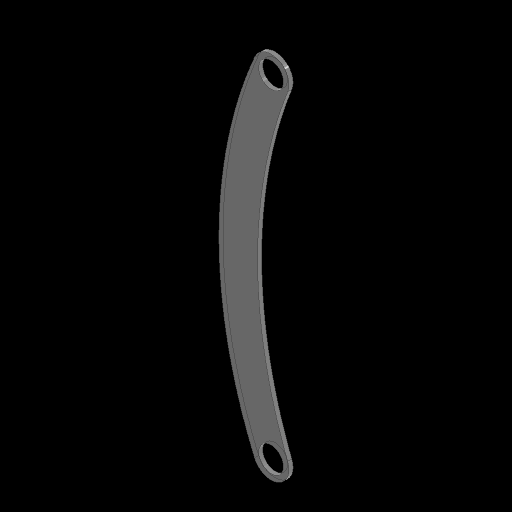
# Autodesk Inventor part: INTK_005_Right bar
Saved by Autodesk Inventor 2027.1 (Build 311270010, 270A)
## iProperties
Created: 2026-11-21
Part Number: INTK_005_Right bar
Material: Polycarbonate, Clear
Document SubType Name: Modeling
Designer: Stanley Ruangsuwan
Density: 1.2 g/cm^3
Appearance: Polycarbonate - Clear
Author: Stanley Ruangsuwan
Autodesk Inventor part; units mm, degrees
ref_plane "YZ Plane" through (0, 0, 0) normal (1, 0, 0) x (0, 1, 0)
ref_plane "XZ Plane" through (0, 0, 0) normal (0, 1, 0) x (-1, 0, 0)
ref_plane "XY Plane" through (0, 0, 0) normal (0, 0, 1) x (1, 0, 0)
sketch "Sketch1" plane through (0, 0, 0) normal (0, 0, 1) x (1, 0, 0)
  line L0 (0, 384.1448) -> (0, 0) construction
  circle A0 centre (0, 384.1448) radius 14.2875
  circle A1 centre (0, 0) radius 14.2875
  circle A2 centre (0, 384.1448) radius 20.6375
  circle A3 centre (0, 0) radius 20.6375
  arc A4 (-18.9672, 392.2782) -> (-18.9672, -8.1334) centre (447.9178, 192.0724) ccw
  arc A5 (19.2271, 376.6465) -> (19.2271, 7.4983) centre (492.5097, 192.0724) ccw
  dimension "d0" = 384.1448
  dimension "d1" = 28.575
  dimension "d2" = 28.575
  dimension "d5" = 6.35
  dimension "d6" = 508
  constraints: 8 point on circle, 6 centre point, 4 tangent, 3 coincident, 2 end point, 2 equal radius, 1 vertical
  measures "d0" distance of L0.start L0.end
  measures "d1" diameter of A0
  measures "d2" diameter of A1
  measures "d5" radial gap between concentric circles of A0 A2
  measures "d6" radius of A5
extrude "Extrusion1" add sketch "Sketch1" along normal blind 4.7625
body "Solid1"
